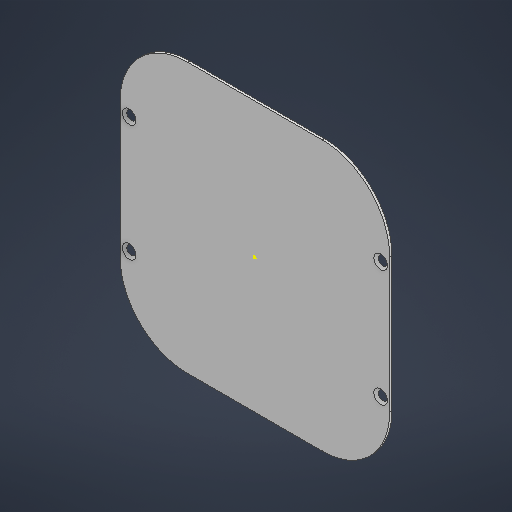
# Autodesk Inventor part: plate cover
Saved by Autodesk Inventor 2025.2 (Build 292293000, 293)
## iProperties
Created: 2024-12-25
Part Number: plate cover
Material: Generic
Document SubType Name: Modeling
Designer: user
Density: 1 g/cm^3
Appearance: Default
Author: user
Autodesk Inventor part; units mm, degrees
ref_plane "YZ Plane" through (0, 0, 0) normal (1, 0, 0) x (0, 1, 0)
ref_plane "XZ Plane" through (0, 0, 0) normal (0, 1, 0) x (-1, 0, 0)
ref_plane "XY Plane" through (0, 0, 0) normal (0, 0, 1) x (1, 0, 0)
sketch "Sketch1" plane through (0, 0, 0) normal (0, 0, 1) x (1, 0, 0)
  circle A0 centre (0, 0) radius 300
  line L0 (150, 300) -> (-150, 300)
  line L1 (-300, 150) -> (-300, -150)
  line L2 (-150, -300) -> (150, -300)
  line L3 (300, -150) -> (300, 150)
  line L4 (300, 300) -> (-300, -300) construction
  line L5 (-300, 300) -> (300, -300) construction
  arc A1 (300, 150) -> (150, 300) centre (150, 150) ccw
  arc A2 (-150, 300) -> (-300, 150) centre (-150, 150) ccw
  arc A3 (-300, -150) -> (-150, -300) centre (-150, -150) ccw
  arc A4 (150, -300) -> (300, -150) centre (150, -150) ccw
  point P0 (300, 0)
  point P1 (0, -300)
  point P2 (-300, 0)
  point P3 (0, 300)
  dimension "d0" = 600
  dimension "d8" = 600
  dimension "d9" = 150
  constraints: 12 end point, 8 point on circle, 8 point on line, 8 tangent, 5 centre point, 3 equal radius, 2 midpoint, 2 parallel, 1 coincident, 1 horizontal, 1 perpendicular
  measures "d0" diameter of A0
  measures "d8" distance of L4.end L5.start
  measures "d9" radius of A1
extrude "Extrusion1" add sketch "Sketch1" along normal blind 5
sketch "Sketch3" plane through (0, 0, 5) normal (0, 0, 1) x (1, 0, 0)
  line L0 (-300, 150) -> (-270, 150)
  line L1 (-270, 150) -> (-270, 110)
  line L2 (-270, 110) -> (-300, 110)
  line L3 (-300, 110) -> (-300, 150)
  circle A0 centre (-280, 130) radius 7.5
  point P0 (0, 0)
  dimension "d10" = 30
  dimension "d11" = 40
  dimension "d12" = 15
  dimension "d34" = 20
  constraints: 8 end point, 2 parallel, 1 centre point, 1 horizontal, 1 perpendicular
  measures "d10" distance of L1.end L2.end
  measures "d11" distance of L0.end L1.end
  measures "d12" diameter of A0
  measures "d34" distance from line of L3 A0.centre
sketch "Sketch4" plane through (0, 0, 5) normal (0, 0, 1) x (1, 0, 0)
  point P0 (0, 0)
hole "Hole1" at (-280, 130, 5) direction (0, 0, -1) diameter 15 end through all countersink diameter 30 countersink angle 90
pattern_linear "Rectangular Pattern2" count 2 spacing 560 along (1, 0, 0) count 2 spacing 260 along (0, -1, 0) of "Hole1"
body "Solid1"
